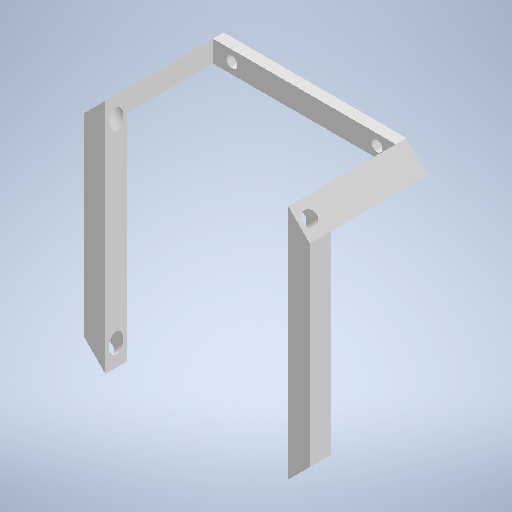
# Autodesk Inventor part: Support_leds
Saved by Autodesk Inventor 2025 (Build 290162000, 162)
## iProperties
Created: 2026-10-28
Part Number: Support_leds
Material: Generic
Document SubType Name: Modeling
Designer: diego
Density: 1 g/cm^3
Appearance: Default
Author: diego
Autodesk Inventor part; units mm, degrees
ref_plane "YZ Plane" through (0, 0, 0) normal (1, 0, 0) x (0, 1, 0)
ref_plane "XZ Plane" through (0, 0, 0) normal (0, 1, 0) x (-1, 0, 0)
ref_plane "XY Plane" through (0, 0, 0) normal (0, 0, 1) x (1, 0, 0)
sketch "Sketch1" plane through (0, 0, 0) normal (0, 0, 1) x (1, 0, 0)
  line L0 (20.25, 0) -> (-20.25, 0) construction
  circle A0 centre (20.25, 0) radius 1.5
  circle A1 centre (-20.25, 0) radius 1.5
  line L1 (31.5, -3) -> (-31.5, -3)
  line L2 (-31.5, -3) -> (-31.5, 3)
  line L3 (-31.5, 3) -> (31.5, 3)
  line L4 (31.5, 3) -> (31.5, -3)
  line L5 (31.5, -3) -> (-31.5, 3) construction
  line L6 (-31.5, -3) -> (31.5, 3) construction
  point P0 (0, 0)
  point P1 (0, 0)
  dimension "d0" = 40.5
  dimension "d1" = 3
  dimension "d2" = 3
  dimension "d3" = 63
  dimension "d4" = 6
  constraints: 14 end point, 3 coincident, 3 midpoint, 2 centre point, 2 horizontal, 2 parallel, 1 perpendicular
  measures "d0" distance of L0.start L0.end
  measures "d1" diameter of A0
  measures "d2" diameter of A1
  measures "d3" distance of L2.end L3.end
  measures "d4" distance between parallel lines of L1 L3
extrude "Extrusion1" add sketch "Sketch1" along normal blind 3
sketch "Sketch2" plane through (0, 0, 3) normal (0, 0, 1) x (1, 0, 0)
  line L0 (31.5, 3) -> (-31.5, 3) projected
  line L1 (-31.5, 3) -> (-31.5, -3) projected
  line L2 (-31.5, -3) -> (31.5, -3) projected
  line L3 (31.5, -3) -> (31.5, 3) projected
  circle A0 centre (-20.25, 0) radius 1.5 projected
  circle A1 centre (20.25, 0) radius 1.5 projected
  line L4 (-25, -3) -> (25, -3)
  line L5 (25, -3) -> (25, 3)
  line L6 (25, 3) -> (-25, 3)
  line L7 (-25, 3) -> (-25, -3)
  line L8 (-25, -3) -> (25, 3) construction
  line L9 (25, -3) -> (-25, 3) construction
  line L10 (-31.5, 3) -> (-25.5, 3)
  line L11 (-25.5, 3) -> (-25.5, -3)
  line L12 (-25.5, -3) -> (-31.5, -3)
  line L13 (-31.5, -3) -> (-31.5, 3)
  line L14 (31.5, 3) -> (25.5, 3)
  line L15 (25.5, 3) -> (25.5, -3)
  line L16 (25.5, -3) -> (31.5, -3)
  line L17 (31.5, -3) -> (31.5, 3)
  point P0 (0, 0)
  dimension "d7" = 50
  dimension "d8" = 6
  dimension "d9" = 6
  dimension "d10" = 6
  dimension "d11" = 6
  constraints: 28 end point, 6 parallel, 3 horizontal, 3 perpendicular, 2 midpoint, 1 point on line
  measures "d7" distance of L6.end L5.end
  measures "d8" distance of L11.end L12.end
  measures "d9" distance of L10.end L11.end
  measures "d10" distance of L16.end L15.end
  measures "d11" distance of L15.end L14.end
extrude "Extrusion2" add sketch "Sketch2" along normal blind 30 contours L3 L2 L15 L0 | L11 L2 L1 L0
sketch "Sketch3" plane through (-31.5, -3, 0) normal (0, -1, 0) x (1, 0, 0)
  line L0 (0, 0) -> (63, 0) projected
  line L1 (63, 0) -> (63, 33) projected
  line L2 (57, 33) -> (63, 33) projected
  line L3 (57, 3) -> (57, 33) projected
  line L4 (6, 3) -> (57, 3) projected
  line L5 (6, 3) -> (6, 33) projected
  line L6 (0, 33) -> (6, 33) projected
  line L7 (0, 0) -> (0, 33) projected
  line L8 (63, 33) -> (57, 33)
  line L9 (57, 33) -> (57, 27)
  line L10 (57, 27) -> (63, 27)
  line L11 (63, 27) -> (63, 33)
  line L12 (6, 3) -> (6, 33) projected
  line L13 (6, 33) -> (0, 33)
  line L14 (0, 33) -> (0, 27)
  line L15 (0, 27) -> (6, 27)
  line L16 (6, 27) -> (6, 33)
  point P0 (31.5, 0)
  dimension "d14" = 6
  dimension "d15" = 6
  dimension "d16" = 6
  constraints: 16 end point, 4 parallel, 2 horizontal, 2 perpendicular, 1 point on line
  measures "d14" distance of L9.end L8.end
  measures "d15" distance of L15.end L14.end
  measures "d16" distance of L14.end L13.end
extrude "Extrusion3" add sketch "Sketch3" along normal blind 60 contours L7 L6 L5 L15 | L10 L3 L2 L1
chamfer "Chamfer1" distance 6 angle 45 4 edges at (31.5, 3, 16.5) (-31.5, 3, 16.5) (-31.5, -63, 30) (31.5, -63, 30)
sketch "Sketch4" plane through (25.5, 3, 3) normal (0.7071, 0.7071, 0) x (-0.7071, 0.7071, 0)
  line L0 (0, 30) -> (-8.4853, 30) projected
  line L1 (-8.4853, 30) -> (-8.4853, 24) projected
  line L2 (-8.4853, -3) -> (-8.4853, 24) projected
  line L3 (-8.4853, -3) -> (0, -3) projected
  line L4 (0, -3) -> (0, 0) projected
  line L5 (0, 0) -> (0, 30) projected
  line L6 (-4.2426, 30) -> (-4.2426, -3) construction
  circle A0 centre (-4.2426, 27) radius 2
  point P0 (15.9099, -3)
  dimension "d22" = 4
  dimension "d23" = 3
  constraints: 2 end point, 2 midpoint, 1 centre point, 1 point on line
  measures "d22" diameter of A0
  measures "d23" distance from line of L0 A0.centre
extrude "Extrusion4" cut sketch "Sketch4" against normal blind 60 contours A0
sketch "Sketch5" plane through (25.5, -63, 33) normal (0.7071, -0.7071, 0) x (-0.7071, -0.7071, 0)
  line L0 (-8.4853, 0) -> (0, 0) projected
  line L1 (0, 0) -> (0, 6) projected
  line L2 (0, 6) -> (-8.4853, 6) projected
  line L3 (-8.4853, 6) -> (-8.4853, 0) projected
  line L4 (-4.2426, 0) -> (-4.2426, 6) construction
  circle A0 centre (-4.2426, 3) radius 2
  point P0 (-26.5165, 33)
  dimension "d26" = 4
  constraints: 3 midpoint, 2 end point, 1 centre point
  measures "d26" diameter of A0
extrude "Extrusion5" cut sketch "Sketch5" against normal blind 60 contours A0
sketch "Sketch6" plane through (-25.5, 3, 3) normal (-0.7071, 0.7071, 0) x (-0.7071, -0.7071, 0)
  line L0 (8.4853, 30) -> (0, 30) projected
  line L1 (0, 0) -> (0, 30) projected
  line L2 (0, 0) -> (0, -3) projected
  line L3 (0, -3) -> (8.4853, -3) projected
  line L4 (8.4853, -3) -> (8.4853, 24) projected
  line L5 (8.4853, 24) -> (8.4853, 30) projected
  line L6 (4.2426, -3) -> (4.2426, 30) construction
  line L7 (8.4853, 30) -> (0, 30) projected
  circle A0 centre (4.2426, 27) radius 2
  point P0 (-15.9099, -3)
  dimension "d29" = 4
  dimension "d30" = 3
  constraints: 2 end point, 2 midpoint, 1 centre point, 1 point on line
  measures "d29" diameter of A0
  measures "d30" distance from line of L0 A0.centre
extrude "Extrusion6" cut sketch "Sketch6" against normal blind 60 contours A0
sketch "Sketch7" plane through (-25.5, -63, 33) normal (-0.7071, -0.7071, 0) x (-0.7071, 0.7071, 0)
  line L0 (8.4853, 6) -> (0, 6) projected
  line L1 (0, 6) -> (0, 0) projected
  line L2 (0, 0) -> (8.4853, 0) projected
  line L3 (8.4853, 0) -> (8.4853, 6) projected
  line L4 (4.2426, 6) -> (4.2426, 0) construction
  circle A0 centre (4.2426, 3) radius 2
  point P0 (26.5165, 33)
  dimension "d33" = 4
  constraints: 3 midpoint, 2 end point, 1 centre point
  measures "d33" diameter of A0
extrude "Extrusion7" cut sketch "Sketch7" against normal blind 60 contours A0
body "Solid1"
